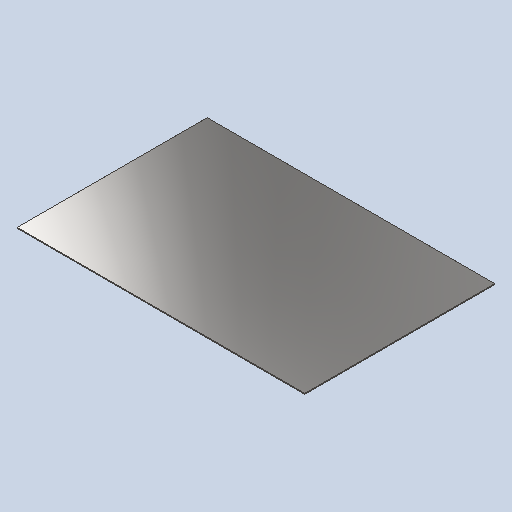
# Autodesk Inventor part: RDS-1201 Bunker Side Wall
Saved by Autodesk Inventor 2026.2 (Build 302298000, 298)
## iProperties
Created: 2026-10-18
Part Number: RDS-1201 Bunker Side Wall
Material: Stainless Steel, Austenitic
Description: Bunker side wall, AISI 304 2 mm
Document SubType Name: Sheet Metal
Designer: admin
Stock Number: Бункер — боковая стенка (×2)
Density: 8 g/cm^3
Flat Pattern Width: 69 cm
Flat Pattern Length: 45.6 cm
Flat Pattern Area: 3146.4 cm^2
Sheet Metal Rule: Default
Sheet Metal Width: 690,000 mm
Sheet Metal Length: 456,000 mm
Sheet Metal Area: 314640,000 mm^2
Appearance: Semi-Polished
Author: admin
Autodesk Inventor part; units mm, degrees
ref_plane "YZ Plane" through (0, 0, 0) normal (1, 0, 0) x (0, 1, 0)
ref_plane "XZ Plane" through (0, 0, 0) normal (0, 1, 0) x (-1, 0, 0)
ref_plane "XY Plane" through (0, 0, 0) normal (0, 0, 1) x (1, 0, 0)
sketch "Sketch1" plane through (0, 0, 0) normal (0, 1, 0) x (-1, 0, 0)
  line L0 (490, -250) -> (-200, -250)
  line L1 (-200, -250) -> (-200, 206)
  line L2 (-200, 206) -> (490, 206)
  line L3 (490, 206) -> (490, -250)
  dimension "d0" = 690
  dimension "d1" = 456
  measures "d0" distance of L0.start L0.end
  measures "d1" distance of L0.end L1.end
extrude "Plate1" add sketch "Sketch1" along normal blind 2
equation "\"d0\" = Side1201_Height"
equation "\"d1\" = Side1201_Length"
equation "\"d2\" = Thickness"
equation "\"BendRadius\" = Thickness"
equation "\"BendReliefWidth\" = Thickness"
equation "\"BendReliefDepth\" = 0.5 * Thickness"
equation "\"CornerReliefSize\" = 4 * Thickness"
equation "\"MinimumRemnant\" = 2 * Thickness"
equation "\"TransitionRadius\" = BendRadius"
equation "\"JacobiRadiusSize\" = BendRadius"
equation "\"GapSize\" = Thickness"
equation "\"Side1201_Height\" = 690"
equation "\"Side1201_Length\" = 456"
equation "\"Thickness\" = 2"
body "Solid1"
